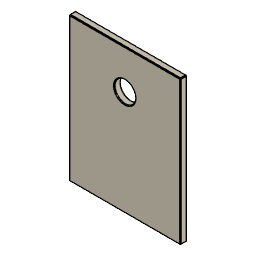
ceramic_heat-conducting_gasket_17x1x22_TO-220 (Autodesk Fusion 360 design; units mm, degrees)
part number: 2026-02-22-20-02-24-277
Autodesk Fusion 360 part; units mm, degrees
sketch "Sketch1" plane through (0, 0, 0) normal (0, 0, 1) x (1, 0, 0)
  line L0 (-8.5, 0.5) -> (8.5, 0.5)
  line L1 (8.5, 0.5) -> (8.5, -0.5)
  line L2 (8.5, -0.5) -> (-8.5, -0.5)
  line L3 (-8.5, -0.5) -> (-8.5, 0.5)
  line L4 (-8.5, 0.5) -> (8.5, -0.5) construction
  line L5 (8.5, 0.5) -> (-8.5, -0.5) construction
  dimension "d1" = 17
  dimension "d2" = 1
  constraint horizontal L0
  constraint perpendicular L0 L1
  constraint parallel L0 L2
  constraint parallel L1 L3
  constraint coincident L4 origin
  constraint coincident L5 origin
  measures "d1" distance of L1.end L2.end
  measures "d2" distance of L0.end L1.end
extrude "Extrude1" add sketch "Sketch1" along normal blind 22
sketch "Sketch2" plane through (0, -0.5, 0) normal (0, -1, 0) x (1, 0, 0)
  line L0 (-8.5, 0) -> (8.5, 0)
  line L1 (8.5, 0) -> (8.5, 22)
  line L2 (8.5, 22) -> (-8.5, 22)
  line L3 (-8.5, 22) -> (-8.5, 0)
  line L4 (-10, 16) -> (10, 16) construction
  line L5 (0, 1.75) -> (0, 22.5) construction
  line L6 (0, 0) -> (0, 22) construction
  circle A0 centre (0, 16) radius 1.6
  point P0 (0, 16)
  dimension "d5" = 20
  dimension "d6" = 6
  dimension "d7" = 22
  dimension "d8" = 3.2
  constraint perpendicular L3 L4
  constraint symmetric L4.start L4.end L5
  constraint vertical L6
  constraint coincident L6.start origin
  constraint midpoint L4 P0
  constraint coincident P0 A0.centre
  measures "d5" distance of L4.start L4.end
  measures "d6" distance of L2 L4
  measures "d7" distance of L6.start L6.end
  measures "d8" diameter of A0
extrude "Extrude2" cut sketch "Sketch2" against normal blind 1 contours A0
fillet "Fillet1" radius 0.1 14 edges at (8.5, -0.5, 11) (8.5, 0.5, 11) (0, -0.5, 22) (0, 0.5, 22) (-8.5, 0, 22) (-8.5, -0.5, 11) (-8.5, 0.5, 11) (8.5, 0, 22) (0, -0.5, 0) (8.5, 0, 0) (0, 0.5, 0) (-8.5, 0, 0) (-1.4917, -0.5, 16.5786) (-1.4917, 0.5, 15.4214)
